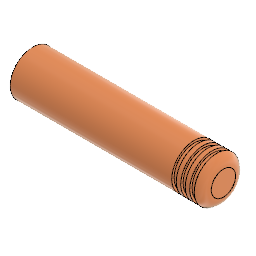
Pin ssg (Autodesk Fusion 360 design; units mm, degrees)
Autodesk Fusion 360 part; units mm, degrees
sketch "Sketch1" plane through (0, 0, 0) normal (1, 0, 0) x (0, 1, 0)
  circle A0 centre (0, 0) radius 10
  dimension "d1" = 20
  constraint coincident A0.centre origin
  measures "d1" diameter of A0
extrude "Extrude1" add sketch "Sketch1" along normal blind 85
sketch "Sketch2" plane through (0, 0, 0) normal (0, 0, 1) x (1, 0, 0)
  line L0 (82, 10) -> (80, 10)
  line L1 (80, 10) -> (80, 9)
  line L2 (80, 9) -> (82, 9)
  line L3 (82, 9) -> (82, 10)
  line L4 (78, 10) -> (76, 10)
  line L5 (76, 10) -> (76, 9)
  line L6 (76, 9) -> (78, 9)
  line L7 (78, 9) -> (78, 10)
  line L8 (74, 10) -> (72, 10)
  line L9 (72, 10) -> (72, 9)
  line L10 (72, 9) -> (74, 9)
  line L11 (74, 9) -> (74, 10)
  constraint horizontal L0
  constraint vertical L1
  constraint horizontal L2
  constraint vertical L3
  constraint horizontal L4
  constraint vertical L5
  constraint horizontal L6
  constraint vertical L7
  constraint horizontal L8
  constraint vertical L9
  constraint horizontal L10
  constraint vertical L11
revolve "Revolve1" cut sketch "Sketch2" angle 360 about axis through (0, 0, 0) along (-1, 0, 0)
fillet "Fillet1" radius 5 1 edges at (85, -9.3233, -3.6162)
